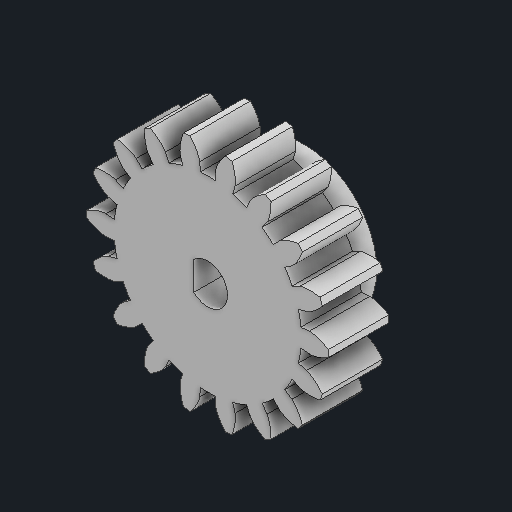
# Autodesk Inventor part: P2-01 Input pinion 18 teeth
Saved by Autodesk Inventor 2027.1 (Build 311270010, 270A)
## iProperties
Created: 2026-10-21
Part Number: P2-01 Input pinion 18 teeth
Material: Generic
Document SubType Name: Modeling
Designer: anshi
Mass: 1.48439 g
Surface Area: 12.7558 cm^2
Volume: 1.48439 cm^3
Density: 1 g/cm^3
Appearance: Default
Author: anshi
Autodesk Inventor part; units mm, degrees
ref_plane "Work Plane1" through (0, 0, 3) normal (0, 0, 1) x (1, 0, 0)
ref_plane "Work Plane2" through (-6, 0, 0) normal (1, 0, 0) x (0, 1, 0)
ref_plane "Work Plane3" through (0, 0, 3) normal (0, 0, 1) x (1, 0, 0)
sketch "18T tooth profile" plane through (0, 0, 3) normal (0, 0, 1) x (1, 0, 0)
  line L0 (7.7139, -0.7476) -> (8.4178, -0.8158)
  spline S0 degree 4 poles (8.4178, -0.8158) (8.4249, -0.8166) (8.4598, -0.8183) (8.5186, -0.8166) (8.6175, -0.8076) (8.721, -0.7925) (8.8472, -0.7674) (8.9945, -0.73) (9.1621, -0.678) (9.4279, -0.5801) (9.6634, -0.4715) (9.8549, -0.3687) (9.9959, -0.2852) knots 0 0 0 0 0 0.103825 0.165016 0.2363 0.316306 0.40413 0.499108 0.600725 0.708565 1 1 1 1 1
  arc A0 (9.9959, -0.2852) -> (9.9959, 0.2852) centre (0, 0) ccw
  spline S1 degree 4 poles (9.9959, 0.2852) (9.8547, 0.3686) (9.663, 0.4712) (9.4273, 0.5794) (9.1612, 0.6772) (8.9935, 0.7291) (8.8463, 0.7664) (8.72, 0.7915) (8.6166, 0.8067) (8.518, 0.8159) (8.4595, 0.8177) (8.4247, 0.8164) (8.4178, 0.8158) knots 0 0 0 0 0 0.291665 0.39959 0.501284 0.596327 0.684201 0.764236 0.835518 0.896661 1 1 1 1 1
  line L1 (8.4178, 0.8158) -> (7.7139, 0.7476)
  arc A1 (7.7139, 0.7476) -> (7.5044, 1.9358) centre (0, 0) ccw
  line L2 (7.5044, 1.9358) -> (8.1892, 2.1124)
  spline S2 degree 4 poles (8.1892, 2.1124) (8.1962, 2.1141) (8.2295, 2.1247) (8.2842, 2.1464) (8.374, 2.1888) (8.466, 2.2385) (8.5761, 2.3052) (8.7017, 2.3907) (8.8414, 2.4968) (9.0577, 2.6797) (9.2418, 2.8621) (9.3867, 3.0241) (9.4907, 3.1508) knots 0 0 0 0 0 0.103872 0.165076 0.236367 0.316377 0.404199 0.499172 0.60078 0.708608 1 1 1 1 1
  arc A2 (9.4907, 3.1508) -> (9.2955, 3.6868) centre (0, 0) ccw
  spline S3 degree 4 poles (9.2955, 3.6868) (9.1338, 3.7169) (8.9178, 3.7478) (8.6585, 3.7689) (8.3743, 3.7699) (8.1987, 3.7613) (8.0474, 3.746) (7.9203, 3.7264) (7.8182, 3.7054) (7.7232, 3.6803) (7.6684, 3.6621) (7.6369, 3.6488) (7.6311, 3.6457) knots 0 0 0 0 0 0.29245 0.400638 0.502552 0.597761 0.685734 0.765785 0.836976 0.897879 1 1 1 1 1
  line L3 (7.6311, 3.6457) -> (6.993, 3.3408)
  arc A3 (6.993, 3.3408) -> (6.3897, 4.3857) centre (0, 0) ccw
  line L4 (6.3897, 4.3857) -> (6.9728, 4.7859)
  spline S4 degree 4 poles (6.9728, 4.7859) (6.9787, 4.7899) (7.0065, 4.8113) (7.0504, 4.8503) (7.1203, 4.9209) (7.1898, 4.9991) (7.2704, 5.0994) (7.3592, 5.2227) (7.4542, 5.3702) (7.5949, 5.616) (7.7056, 5.8504) (7.7863, 6.0522) (7.8407, 6.2068) knots 0 0 0 0 0 0.10386 0.165065 0.236357 0.316367 0.404191 0.499165 0.600774 0.708603 1 1 1 1 1
  arc A4 (7.8407, 6.2068) -> (7.474, 6.6438) centre (0, 0) ccw
  spline S5 degree 4 poles (7.474, 6.6438) (7.3117, 6.6167) (7.0983, 6.5719) (6.8474, 6.5032) (6.58, 6.4069) (6.4179, 6.3388) (6.281, 6.2727) (6.1682, 6.2108) (6.0795, 6.1561) (5.9988, 6.1) (5.9535, 6.0641) (5.9283, 6.0408) (5.924, 6.0358) knots 0 0 0 0 0 0.292397 0.400568 0.502466 0.597663 0.685627 0.765676 0.836873 0.897794 1 1 1 1 1
  line L5 (5.924, 6.0358) -> (5.4286, 5.5311)
  arc A5 (5.4286, 5.5311) -> (4.5044, 6.3066) centre (0, 0) ccw
  line L6 (4.5044, 6.3066) -> (4.9154, 6.8821)
  spline S6 degree 4 poles (4.9154, 6.8821) (4.9196, 6.8879) (4.9384, 6.9175) (4.9663, 6.9692) (5.0078, 7.0594) (5.0465, 7.1567) (5.0879, 7.2785) (5.1291, 7.4247) (5.1679, 7.5958) (5.2161, 7.875) (5.2399, 8.1331) (5.2467, 8.3503) (5.245, 8.5141) knots 0 0 0 0 0 0.10386 0.165065 0.236357 0.316368 0.404191 0.499165 0.600774 0.708603 1 1 1 1 1
  arc A6 (5.245, 8.5141) -> (4.7509, 8.7993) centre (0, 0) ccw
  spline S7 degree 4 poles (4.7509, 8.7993) (4.6078, 8.7186) (4.4227, 8.6037) (4.2106, 8.4535) (3.9924, 8.2719) (3.8635, 8.1525) (3.7574, 8.0436) (3.6726, 7.9468) (3.6079, 7.865) (3.551, 7.7844) (3.5206, 7.7349) (3.5048, 7.7042) (3.5024, 7.6979) knots 0 0 0 0 0 0.292116 0.400191 0.502009 0.597144 0.685073 0.765116 0.836349 0.897366 1 1 1 1 1
  line L7 (3.5024, 7.6979) -> (3.2095, 7.0542)
  arc A7 (3.2095, 7.0542) -> (2.0757, 7.4668) centre (0, 0) ccw
  line L8 (2.0757, 7.4668) -> (2.2652, 8.1482)
  spline S8 degree 4 poles (2.2652, 8.1482) (2.2671, 8.1551) (2.2746, 8.1893) (2.2832, 8.2475) (2.2913, 8.3465) (2.2944, 8.4511) (2.2916, 8.5797) (2.2804, 8.7312) (2.2583, 8.9053) (2.2081, 9.184) (2.1422, 9.4347) (2.0744, 9.6412) (2.0167, 9.7945) knots 0 0 0 0 0 0.103859 0.165063 0.236355 0.316366 0.40419 0.499164 0.600774 0.708603 1 1 1 1 1
  arc A8 (2.0167, 9.7945) -> (1.4549, 9.8936) centre (0, 0) ccw
  spline S9 degree 4 poles (1.4549, 9.8936) (1.3479, 9.7688) (1.2131, 9.5975) (1.0649, 9.3839) (0.9219, 9.1385) (0.8414, 8.9822) (0.779, 8.8437) (0.7324, 8.7237) (0.6996, 8.6247) (0.6739, 8.5295) (0.6624, 8.4726) (0.6583, 8.4384) (0.6583, 8.4316) knots 0 0 0 0 0 0.292151 0.400234 0.502054 0.597186 0.685104 0.765131 0.83634 0.897326 1 1 1 1 1
  line L9 (0.6583, 8.4316) -> (0.6033, 7.7265)
  arc A9 (0.6033, 7.7265) -> (-0.6033, 7.7265) centre (0, 0) ccw
  line L10 (-0.6033, 7.7265) -> (-0.6583, 8.4316)
  spline S10 degree 4 poles (-0.6583, 8.4316) (-0.6588, 8.4387) (-0.6635, 8.4734) (-0.6754, 8.531) (-0.7015, 8.6268) (-0.7345, 8.7261) (-0.7811, 8.8461) (-0.8434, 8.9846) (-0.9237, 9.1406) (-1.0662, 9.3854) (-1.2138, 9.5984) (-1.3482, 9.7692) (-1.4549, 9.8936) knots 0 0 0 0 0 0.103856 0.165061 0.236354 0.316365 0.40419 0.499164 0.600774 0.708603 1 1 1 1 1
  arc A10 (-1.4549, 9.8936) -> (-2.0167, 9.7945) centre (0, 0) ccw
  spline S11 degree 4 poles (-2.0167, 9.7945) (-2.0745, 9.6411) (-2.1425, 9.4345) (-2.2085, 9.1837) (-2.2589, 8.9048) (-2.281, 8.7307) (-2.2922, 8.5792) (-2.295, 8.4505) (-2.2919, 8.3459) (-2.2837, 8.2471) (-2.275, 8.1891) (-2.2673, 8.155) (-2.2652, 8.1482) knots 0 0 0 0 0 0.291535 0.399409 0.501055 0.596055 0.683892 0.763902 0.835177 0.896344 1 1 1 1 1
  line L11 (-2.2652, 8.1482) -> (-2.0757, 7.4668)
  arc A11 (-2.0757, 7.4668) -> (-3.2095, 7.0542) centre (0, 0) ccw
  line L12 (-3.2095, 7.0542) -> (-3.5024, 7.6979)
  spline S12 degree 4 poles (-3.5024, 7.6979) (-3.5054, 7.7044) (-3.5216, 7.7354) (-3.5525, 7.7854) (-3.6099, 7.8664) (-3.6748, 7.9485) (-3.7596, 8.0453) (-3.8656, 8.1541) (-3.9943, 8.2733) (-4.212, 8.4546) (-4.4235, 8.6043) (-4.6082, 8.7189) (-4.7509, 8.7993) knots 0 0 0 0 0 0.103804 0.165006 0.236301 0.316317 0.404147 0.499129 0.600746 0.708584 1 1 1 1 1
  arc A12 (-4.7509, 8.7993) -> (-5.245, 8.5141) centre (0, 0) ccw
  spline S13 degree 4 poles (-5.245, 8.5141) (-5.2468, 8.3503) (-5.24, 8.133) (-5.2162, 7.8749) (-5.1681, 7.5957) (-5.1293, 7.4246) (-5.088, 7.2784) (-5.0466, 7.1566) (-5.008, 7.0593) (-4.9664, 6.9691) (-4.9385, 6.9174) (-4.9196, 6.8879) (-4.9154, 6.8821) knots 0 0 0 0 0 0.291409 0.399242 0.500854 0.595829 0.683653 0.763662 0.834951 0.896151 1 1 1 1 1
  line L13 (-4.9154, 6.8821) -> (-4.5044, 6.3066)
  arc A13 (-4.5044, 6.3066) -> (-5.4286, 5.5311) centre (0, 0) ccw
  line L14 (-5.4286, 5.5311) -> (-5.924, 6.0358)
  spline S14 degree 4 poles (-5.924, 6.0358) (-5.9291, 6.0406) (-5.955, 6.0642) (-6.0011, 6.1004) (-6.0827, 6.1569) (-6.1718, 6.2117) (-6.2846, 6.2737) (-6.4214, 6.3397) (-6.5831, 6.4078) (-6.8496, 6.5038) (-7.0996, 6.5723) (-7.3123, 6.6169) (-7.474, 6.6438) knots 0 0 0 0 0 0.103643 0.164832 0.236129 0.316155 0.404003 0.499007 0.600649 0.708513 1 1 1 1 1
  arc A14 (-7.474, 6.6438) -> (-7.8407, 6.2068) centre (0, 0) ccw
  spline S15 degree 4 poles (-7.8407, 6.2068) (-7.7861, 6.0522) (-7.7051, 5.8505) (-7.5941, 5.6161) (-7.4531, 5.3703) (-7.3579, 5.2229) (-7.2691, 5.0996) (-7.1885, 4.9993) (-7.1191, 4.9211) (-7.0494, 4.8506) (-7.0059, 4.8115) (-6.9783, 4.7901) (-6.9728, 4.7859) knots 0 0 0 0 0 0.291603 0.39951 0.50119 0.596226 0.684098 0.764138 0.835433 0.896597 1 1 1 1 1
  line L15 (-6.9728, 4.7859) -> (-6.3897, 4.3857)
  arc A15 (-6.3897, 4.3857) -> (-6.993, 3.3408) centre (0, 0) ccw
  line L16 (-6.993, 3.3408) -> (-7.6311, 3.6457)
  spline S16 degree 4 poles (-7.6311, 3.6457) (-7.6374, 3.6483) (-7.6697, 3.6614) (-7.7252, 3.6795) (-7.8209, 3.7045) (-7.9233, 3.7256) (-8.0505, 3.7452) (-8.2017, 3.7605) (-8.377, 3.7692) (-8.6605, 3.7684) (-8.919, 3.7475) (-9.1343, 3.7168) (-9.2955, 3.6868) knots 0 0 0 0 0 0.103142 0.164277 0.235566 0.315618 0.403514 0.498583 0.600306 0.70826 1 1 1 1 1
  arc A16 (-9.2955, 3.6868) -> (-9.4907, 3.1508) centre (0, 0) ccw
  spline S17 degree 4 poles (-9.4907, 3.1508) (-9.386, 3.0242) (-9.2404, 2.8623) (-9.0553, 2.6801) (-8.8381, 2.4973) (-8.698, 2.3912) (-8.5723, 2.3058) (-8.4622, 2.2391) (-8.3705, 2.1894) (-8.2815, 2.1472) (-8.2281, 2.1254) (-8.1951, 2.1146) (-8.1892, 2.1124) knots 0 0 0 0 0 0.292263 0.400404 0.502291 0.597498 0.685494 0.765599 0.836875 0.897903 1 1 1 1 1
  line L17 (-8.1892, 2.1124) -> (-7.5044, 1.9358)
  arc A17 (-7.5044, 1.9358) -> (-7.7139, 0.7476) centre (0, 0) ccw
  line L18 (-7.7139, 0.7476) -> (-8.4178, 0.8158)
  spline S18 degree 4 poles (-8.4178, 0.8158) (-8.4247, 0.8159) (-8.4596, 0.8173) (-8.518, 0.8152) (-8.6166, 0.806) (-8.72, 0.7907) (-8.8463, 0.7656) (-8.9935, 0.7283) (-9.1612, 0.6765) (-9.4273, 0.5789) (-9.663, 0.4709) (-9.8547, 0.3685) (-9.9959, 0.2852) knots 0 0 0 0 0 0.103304 0.164462 0.235759 0.315807 0.40369 0.498739 0.600434 0.708356 1 1 1 1 1
  arc A18 (-9.9959, 0.2852) -> (-9.9959, -0.2852) centre (0, 0) ccw
  spline S19 degree 4 poles (-9.9959, -0.2852) (-9.8546, -0.3689) (-9.6627, -0.4718) (-9.4268, -0.5806) (-9.1605, -0.6787) (-8.9927, -0.7308) (-8.8454, -0.7682) (-8.7191, -0.7933) (-8.6158, -0.8084) (-8.5174, -0.8174) (-8.4592, -0.8188) (-8.4244, -0.8172) (-8.4178, -0.8158) knots 0 0 0 0 0 0.291964 0.399985 0.501758 0.59686 0.684769 0.764813 0.836073 0.897155 1 1 1 1 1
  line L19 (-8.4178, -0.8158) -> (-7.7139, -0.7476)
  arc A19 (-7.7139, -0.7476) -> (-7.5044, -1.9358) centre (0, 0) ccw
  line L20 (-7.5044, -1.9358) -> (-8.1892, -2.1124)
  spline S20 degree 4 poles (-8.1892, -2.1124) (-8.1947, -2.1125) (-8.2276, -2.1229) (-8.2801, -2.1433) (-8.3684, -2.1849) (-8.4598, -2.2342) (-8.5699, -2.3009) (-8.6957, -2.3866) (-8.8361, -2.4932) (-9.0538, -2.6771) (-9.2395, -2.8605) (-9.3857, -3.0234) (-9.4907, -3.1508) knots 0 0 0 0 0 0.09996 0.160726 0.231929 0.312096 0.400266 0.495737 0.597968 0.706518 1 1 1 1 1
  arc A20 (-9.4907, -3.1508) -> (-9.2955, -3.6868) centre (0, 0) ccw
  spline S21 degree 4 poles (-9.2955, -3.6868) (-9.1341, -3.7169) (-8.9185, -3.7477) (-8.6596, -3.7689) (-8.3759, -3.7698) (-8.2004, -3.7612) (-8.0492, -3.746) (-7.922, -3.7263) (-7.8197, -3.7053) (-7.7242, -3.6802) (-7.6692, -3.6619) (-7.637, -3.6487) (-7.6311, -3.6457) knots 0 0 0 0 0 0.292049 0.400106 0.501912 0.597046 0.684982 0.765044 0.83631 0.897376 1 1 1 1 1
  line L21 (-7.6311, -3.6457) -> (-6.993, -3.3408)
  arc A21 (-6.993, -3.3408) -> (-6.3897, -4.3857) centre (0, 0) ccw
  line L22 (-6.3897, -4.3857) -> (-6.9728, -4.7859)
  spline S22 degree 4 poles (-6.9728, -4.7859) (-6.9772, -4.7874) (-7.0043, -4.8086) (-7.0455, -4.845) (-7.1136, -4.9138) (-7.1823, -4.9911) (-7.2629, -5.0915) (-7.352, -5.2151) (-7.4478, -5.3634) (-7.5902, -5.6111) (-7.7027, -5.8474) (-7.785, -6.0509) (-7.8407, -6.2068) knots 0 0 0 0 0 0.097919 0.158492 0.229679 0.30995 0.398313 0.494047 0.596595 0.705504 1 1 1 1 1
  arc A22 (-7.8407, -6.2068) -> (-7.474, -6.6438) centre (0, 0) ccw
  spline S23 degree 4 poles (-7.474, -6.6438) (-7.312, -6.6167) (-7.0989, -6.5717) (-6.8484, -6.5028) (-6.5815, -6.4064) (-6.4196, -6.3383) (-6.2827, -6.2722) (-6.1699, -6.2102) (-6.081, -6.1555) (-5.9999, -6.0994) (-5.9544, -6.0637) (-5.9286, -6.0403) (-5.924, -6.0358) knots 0 0 0 0 0 0.292153 0.40025 0.502095 0.597262 0.685224 0.765305 0.836574 0.89762 1 1 1 1 1
  line L23 (-5.924, -6.0358) -> (-5.4286, -5.5311)
  arc A23 (-5.4286, -5.5311) -> (-4.5044, -6.3066) centre (0, 0) ccw
  line L24 (-4.5044, -6.3066) -> (-4.9154, -6.8821)
  spline S24 degree 4 poles (-4.9154, -6.8821) (-4.9187, -6.8847) (-4.9368, -6.9139) (-4.9626, -6.9616) (-5.0027, -7.0491) (-5.0408, -7.1451) (-5.0822, -7.267) (-5.1237, -7.4137) (-5.1631, -7.586) (-5.2125, -7.8677) (-5.2377, -8.1287) (-5.2458, -8.3483) (-5.245, -8.5141) knots 0 0 0 0 0 0.096711 0.157178 0.228361 0.308696 0.397174 0.493063 0.595796 0.704915 1 1 1 1 1
  arc A24 (-5.245, -8.5141) -> (-4.7509, -8.7993) centre (0, 0) ccw
  spline S25 degree 4 poles (-4.7509, -8.7993) (-4.608, -8.7183) (-4.423, -8.6031) (-4.211, -8.4525) (-3.9931, -8.2704) (-3.8642, -8.1509) (-3.7582, -8.0419) (-3.6733, -7.9451) (-3.6086, -7.8634) (-3.5517, -7.7832) (-3.5212, -7.7343) (-3.505, -7.7036) (-3.5024, -7.6979) knots 0 0 0 0 0 0.2924 0.400583 0.502502 0.59773 0.685737 0.765838 0.837098 0.898093 1 1 1 1 1
  line L25 (-3.5024, -7.6979) -> (-3.2095, -7.0542)
  arc A25 (-3.2095, -7.0542) -> (-2.0757, -7.4668) centre (0, 0) ccw
  line L26 (-2.0757, -7.4668) -> (-2.2652, -8.1482)
  spline S26 degree 4 poles (-2.2652, -8.1482) (-2.2668, -8.1516) (-2.2737, -8.1853) (-2.2813, -8.2383) (-2.289, -8.334) (-2.2917, -8.437) (-2.289, -8.5658) (-2.2779, -8.7178) (-2.2561, -8.8933) (-2.2064, -9.1752) (-2.1412, -9.4294) (-2.0739, -9.6388) (-2.0167, -9.7945) knots 0 0 0 0 0 0.095787 0.156186 0.227377 0.307769 0.39634 0.492348 0.595221 0.704494 1 1 1 1 1
  arc A26 (-2.0167, -9.7945) -> (-1.4549, -9.8936) centre (0, 0) ccw
  spline S27 degree 4 poles (-1.4549, -9.8936) (-1.3483, -9.7684) (-1.2141, -9.5966) (-1.0666, -9.3824) (-0.9242, -9.1366) (-0.8441, -8.9801) (-0.7817, -8.8415) (-0.7351, -8.7215) (-0.7022, -8.6226) (-0.6761, -8.5279) (-0.664, -8.4719) (-0.6592, -8.4376) (-0.6583, -8.4316) knots 0 0 0 0 0 0.292573 0.400821 0.5028 0.59808 0.686128 0.766255 0.837518 0.89848 1 1 1 1 1
  line L27 (-0.6583, -8.4316) -> (-0.6033, -7.7265)
  arc A27 (-0.6033, -7.7265) -> (0.6033, -7.7265) centre (0, 0) ccw
  line L28 (0.6033, -7.7265) -> (0.6583, -8.4316)
  spline S28 degree 4 poles (0.6583, -8.4316) (0.6593, -8.4353) (0.6642, -8.4693) (0.6762, -8.5219) (0.7019, -8.6145) (0.7347, -8.7124) (0.7813, -8.8324) (0.8436, -8.9715) (0.9238, -9.1289) (1.0664, -9.3767) (1.2139, -9.5932) (1.3482, -9.7669) (1.4549, -9.8936) knots 0 0 0 0 0 0.096307 0.156774 0.227993 0.308381 0.39692 0.492869 0.595659 0.704827 1 1 1 1 1
  arc A28 (1.4549, -9.8936) -> (2.0167, -9.7945) centre (0, 0) ccw
  spline S29 degree 4 poles (2.0167, -9.7945) (2.074, -9.6407) (2.1414, -9.4335) (2.2067, -9.1821) (2.2564, -8.9027) (2.2782, -8.7283) (2.2893, -8.5768) (2.2921, -8.4481) (2.2892, -8.3438) (2.2813, -8.2456) (2.2735, -8.1884) (2.2662, -8.1545) (2.2652, -8.1482) knots 0 0 0 0 0 0.292256 0.400394 0.502279 0.597483 0.685478 0.765581 0.836857 0.897886 1 1 1 1 1
  line L29 (2.2652, -8.1482) -> (2.0757, -7.4668)
  arc A29 (2.0757, -7.4668) -> (3.2095, -7.0542) centre (0, 0) ccw
  line L30 (3.2095, -7.0542) -> (3.5024, -7.6979)
  spline S30 degree 4 poles (3.5024, -7.6979) (3.5056, -7.703) (3.5219, -7.7335) (3.5525, -7.7819) (3.6094, -7.8618) (3.6743, -7.9434) (3.7591, -8.0402) (3.865, -8.1492) (3.9938, -8.269) (4.2116, -8.4514) (4.4233, -8.6024) (4.6081, -8.7181) (4.7509, -8.7993) knots 0 0 0 0 0 0.101349 0.1623 0.233569 0.313711 0.40178 0.497084 0.59909 0.707364 1 1 1 1 1
  arc A30 (4.7509, -8.7993) -> (5.245, -8.5141) centre (0, 0) ccw
  spline S31 degree 4 poles (5.245, -8.5141) (5.2464, -8.3501) (5.2391, -8.1327) (5.2147, -7.8743) (5.1662, -7.595) (5.1271, -7.4238) (5.0858, -7.2776) (5.0443, -7.1557) (5.0059, -7.0586) (4.9647, -6.9687) (4.9374, -6.9173) (4.9189, -6.8878) (4.9154, -6.8821) knots 0 0 0 0 0 0.291868 0.399868 0.501632 0.596736 0.684657 0.764723 0.83601 0.897119 1 1 1 1 1
  line L31 (4.9154, -6.8821) -> (4.5044, -6.3066)
  arc A31 (4.5044, -6.3066) -> (5.4286, -5.5311) centre (0, 0) ccw
  line L32 (5.4286, -5.5311) -> (5.924, -6.0358)
  spline S32 degree 4 poles (5.924, -6.0358) (5.929, -6.0394) (5.9548, -6.0625) (6.0003, -6.0975) (6.0812, -6.1532) (6.1701, -6.2077) (6.2829, -6.2697) (6.4197, -6.3359) (6.5816, -6.4043) (6.8485, -6.5013) (7.0989, -6.5707) (7.312, -6.6162) (7.474, -6.6438) knots 0 0 0 0 0 0.101611 0.162595 0.233873 0.314007 0.402054 0.497325 0.599288 0.707513 1 1 1 1 1
  arc A32 (7.474, -6.6438) -> (7.8407, -6.2068) centre (0, 0) ccw
  spline S33 degree 4 poles (7.8407, -6.2068) (7.7859, -6.0521) (7.7047, -5.8503) (7.5935, -5.6158) (7.4524, -5.3699) (7.3571, -5.2224) (7.2683, -5.0991) (7.1877, -4.9988) (7.1183, -4.9206) (7.0489, -4.8503) (7.0056, -4.8114) (6.9781, -4.79) (6.9728, -4.7859) knots 0 0 0 0 0 0.29187 0.399871 0.501633 0.596735 0.684654 0.764717 0.836002 0.89711 1 1 1 1 1
  line L33 (6.9728, -4.7859) -> (6.3897, -4.3857)
  arc A33 (6.3897, -4.3857) -> (6.993, -3.3408) centre (0, 0) ccw
  line L34 (6.993, -3.3408) -> (7.6311, -3.6457)
  spline S34 degree 4 poles (7.6311, -3.6457) (7.6376, -3.6483) (7.6699, -3.6615) (7.7256, -3.6796) (7.8215, -3.7048) (7.924, -3.7258) (8.0512, -3.7454) (8.2023, -3.7607) (8.3776, -3.7694) (8.6609, -3.7686) (8.9193, -3.7475) (9.1344, -3.7168) (9.2955, -3.6868) knots 0 0 0 0 0 0.103493 0.16467 0.235968 0.316005 0.403869 0.498893 0.600558 0.708448 1 1 1 1 1
  arc A34 (9.2955, -3.6868) -> (9.4907, -3.1508) centre (0, 0) ccw
  spline S35 degree 4 poles (9.4907, -3.1508) (9.3866, -3.0242) (9.2416, -2.8623) (9.0573, -2.68) (8.8408, -2.4971) (8.701, -2.3911) (8.5755, -2.3056) (8.4654, -2.2389) (8.3734, -2.1892) (8.2837, -2.1468) (8.2292, -2.125) (8.1959, -2.1144) (8.1892, -2.1124) knots 0 0 0 0 0 0.291507 0.399378 0.501026 0.596033 0.683882 0.763909 0.835203 0.896386 1 1 1 1 1
  line L35 (8.1892, -2.1124) -> (7.5044, -1.9358)
  arc A35 (7.5044, -1.9358) -> (7.7139, -0.7476) centre (0, 0) ccw
  point P0 (8.4294, -0.8166)
  point P1 (8.4645, -0.8173)
  point P2 (8.5229, -0.8152)
  point P3 (8.6043, -0.8081)
  point P4 (8.7085, -0.7934)
  point P5 (8.8347, -0.7687)
  point P6 (8.9821, -0.7317)
  point P7 (9.1497, -0.6801)
  point P8 (9.3363, -0.6117)
  point P9 (9.5406, -0.5244)
  point P10 (9.7611, -0.4162)
  point P11 (9.7608, 0.416)
  point P12 (9.5401, 0.5239)
  point P13 (9.3356, 0.611)
  point P14 (9.1488, 0.6792)
  point P15 (8.9811, 0.7307)
  point P16 (8.8337, 0.7677)
  point P17 (8.7075, 0.7924)
  point P18 (8.6034, 0.8072)
  point P19 (8.5221, 0.8145)
  point P20 (8.4639, 0.8168)
  point P21 (8.4291, 0.8164)
  point P22 (8.2004, 2.1157)
  point P23 (8.2335, 2.1272)
  point P24 (8.2877, 2.1492)
  point P25 (8.3618, 2.1839)
  point P26 (8.4546, 2.2334)
  point P27 (8.5647, 2.2998)
  point P28 (8.6906, 2.385)
  point P29 (8.8304, 2.4907)
  point P30 (8.9824, 2.6187)
  point P31 (9.1446, 2.7705)
  point P32 (9.3147, 2.9475)
  point P33 (9.029, 3.7293)
  point P34 (8.7839, 3.7554)
  point P35 (8.5613, 3.7673)
  point P36 (8.3619, 3.7675)
  point P37 (8.1864, 3.7586)
  point P38 (8.0351, 3.7429)
  point P39 (7.9081, 3.723)
  point P40 (7.8055, 3.7013)
  point P41 (7.7271, 3.6803)
  point P42 (7.6724, 3.6625)
  point P43 (7.6409, 3.6502)
  point P44 (6.9822, 4.7928)
  point P45 (7.0094, 4.815)
  point P46 (7.0528, 4.8542)
  point P47 (7.1106, 4.9121)
  point P48 (7.1809, 4.9904)
  point P49 (7.2616, 5.0904)
  point P50 (7.3508, 5.2135)
  point P51 (7.446, 5.3607)
  point P52 (7.5451, 5.533)
  point P53 (7.6455, 5.7311)
  point P54 (7.7449, 5.9555)
  point P55 (7.209, 6.5926)
  point P56 (6.9698, 6.5333)
  point P57 (6.7566, 6.4684)
  point P58 (6.5692, 6.4005)
  point P59 (6.4073, 6.332)
  point P60 (6.2705, 6.2655)
  point P61 (6.158, 6.2034)
  point P62 (6.069, 6.1479)
  point P63 (6.0024, 6.1014)
  point P64 (5.9571, 6.0658)
  point P65 (5.9316, 6.0434)
  point P66 (4.9219, 6.8919)
  point P67 (4.9399, 6.922)
  point P68 (4.9672, 6.9736)
  point P69 (5.0017, 7.0478)
  point P70 (5.041, 7.1454)
  point P71 (5.0827, 7.2671)
  point P72 (5.1243, 7.4132)
  point P73 (5.1635, 7.5841)
  point P74 (5.1977, 7.7799)
  point P75 (5.2243, 8.0004)
  point P76 (5.2409, 8.2453)
  point P77 (4.5196, 8.6609)
  point P78 (4.3153, 8.5236)
  point P79 (4.1372, 8.3899)
  point P80 (3.9845, 8.2621)
  point P81 (3.8558, 8.1425)
  point P82 (3.75, 8.0333)
  point P83 (3.6655, 7.9364)
  point P84 (3.6008, 7.8537)
  point P85 (3.5541, 7.7871)
  point P86 (3.5235, 7.738)
  point P87 (3.507, 7.7079)
  point P88 (2.2679, 8.1596)
  point P89 (2.2745, 8.194)
  point P90 (2.2825, 8.2519)
  point P91 (2.2895, 8.3335)
  point P92 (2.2931, 8.4386)
  point P93 (2.2907, 8.5672)
  point P94 (2.2798, 8.7187)
  point P95 (2.2582, 8.8928)
  point P96 (2.2233, 9.0884)
  point P97 (2.1729, 9.3047)
  point P98 (2.1048, 9.5405)
  point P99 (1.2846, 9.6844)
  point P100 (1.1394, 9.4855)
  point P101 (1.0177, 9.2989)
  point P102 (0.9177, 9.1266)
  point P103 (0.8376, 8.9703)
  point P104 (0.7755, 8.8314)
  point P105 (0.7293, 8.7115)
  point P106 (0.6969, 8.6117)
  point P107 (0.6759, 8.5331)
  point P108 (0.6641, 8.4765)
  point P109 (0.6591, 8.4426)
  point P110 (-0.6596, 8.4432)
  point P111 (-0.6652, 8.4778)
  point P112 (-0.6775, 8.535)
  point P113 (-0.6988, 8.614)
  point P114 (-0.7314, 8.714)
  point P115 (-0.7777, 8.834)
  point P116 (-0.8397, 8.9727)
  point P117 (-0.9195, 9.1288)
  point P118 (-1.0192, 9.3007)
  point P119 (-1.1405, 9.4867)
  point P120 (-1.2852, 9.685)
  point P121 (-2.105, 9.5404)
  point P122 (-2.1733, 9.3044)
  point P123 (-2.2238, 9.088)
  point P124 (-2.2587, 8.8922)
  point P125 (-2.2804, 8.7182)
  point P126 (-2.2913, 8.5666)
  point P127 (-2.2937, 8.438)
  point P128 (-2.2901, 8.3329)
  point P129 (-2.283, 8.2515)
  point P130 (-2.2748, 8.1937)
  point P131 (-2.2681, 8.1595)
  point P132 (-3.5076, 7.7083)
  point P133 (-3.5248, 7.7389)
  point P134 (-3.5559, 7.7884)
  point P135 (-3.6029, 7.8553)
  point P136 (-3.6678, 7.9381)
  point P137 (-3.7523, 8.035)
  point P138 (-3.858, 8.1442)
  point P139 (-3.9864, 8.2636)
  point P140 (-4.1389, 8.3911)
  point P141 (-4.3165, 8.5245)
  point P142 (-4.5202, 8.6613)
  point P143 (-5.2409, 8.2453)
  point P144 (-5.2244, 8.0003)
  point P145 (-5.1978, 7.7798)
  point P146 (-5.1636, 7.584)
  point P147 (-5.1245, 7.4131)
  point P148 (-5.0828, 7.2669)
  point P149 (-5.0411, 7.1453)
  point P150 (-5.0018, 7.0477)
  point P151 (-4.9673, 6.9735)
  point P152 (-4.9399, 6.9219)
  point P153 (-4.9219, 6.8918)
  point P154 (-5.9325, 6.0436)
  point P155 (-5.9591, 6.0663)
  point P156 (-6.0052, 6.1021)
  point P157 (-6.0723, 6.1488)
  point P158 (-6.1616, 6.2044)
  point P159 (-6.2742, 6.2666)
  point P160 (-6.4108, 6.333)
  point P161 (-6.5723, 6.4014)
  point P162 (-6.7592, 6.4691)
  point P163 (-6.9717, 6.5338)
  point P164 (-7.21, 6.5929)
  point P165 (-7.7445, 5.9556)
  point P166 (-7.6449, 5.7312)
  point P167 (-7.5442, 5.5331)
  point P168 (-7.4449, 5.3609)
  point P169 (-7.3495, 5.2137)
  point P170 (-7.2603, 5.0906)
  point P171 (-7.1795, 4.9906)
  point P172 (-7.1093, 4.9123)
  point P173 (-7.0517, 4.8543)
  point P174 (-7.0086, 4.8151)
  point P175 (-6.9818, 4.7929)
  point P176 (-7.6415, 3.6499)
  point P177 (-7.674, 3.662)
  point P178 (-7.7294, 3.6796)
  point P179 (-7.8084, 3.7005)
  point P180 (-7.9112, 3.7222)
  point P181 (-8.0383, 3.7421)
  point P182 (-8.1895, 3.7578)
  point P183 (-8.3647, 3.7668)
  point P184 (-8.5636, 3.7667)
  point P185 (-8.7855, 3.7549)
  point P186 (-9.0298, 3.7291)
  point P187 (-9.3137, 2.9476)
  point P188 (-9.1426, 2.7708)
  point P189 (-8.9797, 2.6191)
  point P190 (-8.8272, 2.4911)
  point P191 (-8.6869, 2.3854)
  point P192 (-8.5609, 2.3003)
  point P193 (-8.4508, 2.2339)
  point P194 (-8.3582, 2.1843)
  point P195 (-8.2846, 2.1496)
  point P196 (-8.2312, 2.1275)
  point P197 (-8.1991, 2.1159)
  point P198 (-8.4291, 0.8161)
  point P199 (-8.4639, 0.8163)
  constraints: 72 end point, 72 point on circle, 36 centre point, 468 other
extrude "Gear face 5 mm" add sketch "18T tooth profile" along normal blind 5
sketch "Lower hub" plane through (0, 0, 0) normal (0, 0, 1) x (1, 0, 0)
  circle A0 centre (0, 0) radius 6
  constraints: 1 centre point
extrude "Hub 3 mm" add sketch "Lower hub" along normal blind 3
sketch "D-bore 3.30 flat 1.15" plane through (0, 0, 0) normal (0, 0, 1) x (1, 0, 0)
  arc A0 (-1.15, -1.1832) -> (-1.15, 1.1832) centre (0, 0) ccw
  line L0 (-1.15, 1.1832) -> (-1.15, -1.1832)
  constraints: 2 end point, 2 point on circle, 1 centre point
extrude "D-bore through" cut sketch "D-bore 3.30 flat 1.15" along normal blind 8
ref_plane "Work Plane4" through (-6, 0, 0) normal (1, 0, 0) x (0, 1, 0)
sketch "M2 radial pilot" plane through (-6, 0, 0) normal (1, 0, 0) x (0, 1, 0)
  circle A0 centre (0, 1.5) radius 0.8
  constraints: 1 centre point
extrude "M2 x 0.4 pilot" cut sketch "M2 radial pilot" along normal blind 5
equation "\"NominalThickness\" = 8"
equation "\"Module\" = 1"
body "Solid2"
